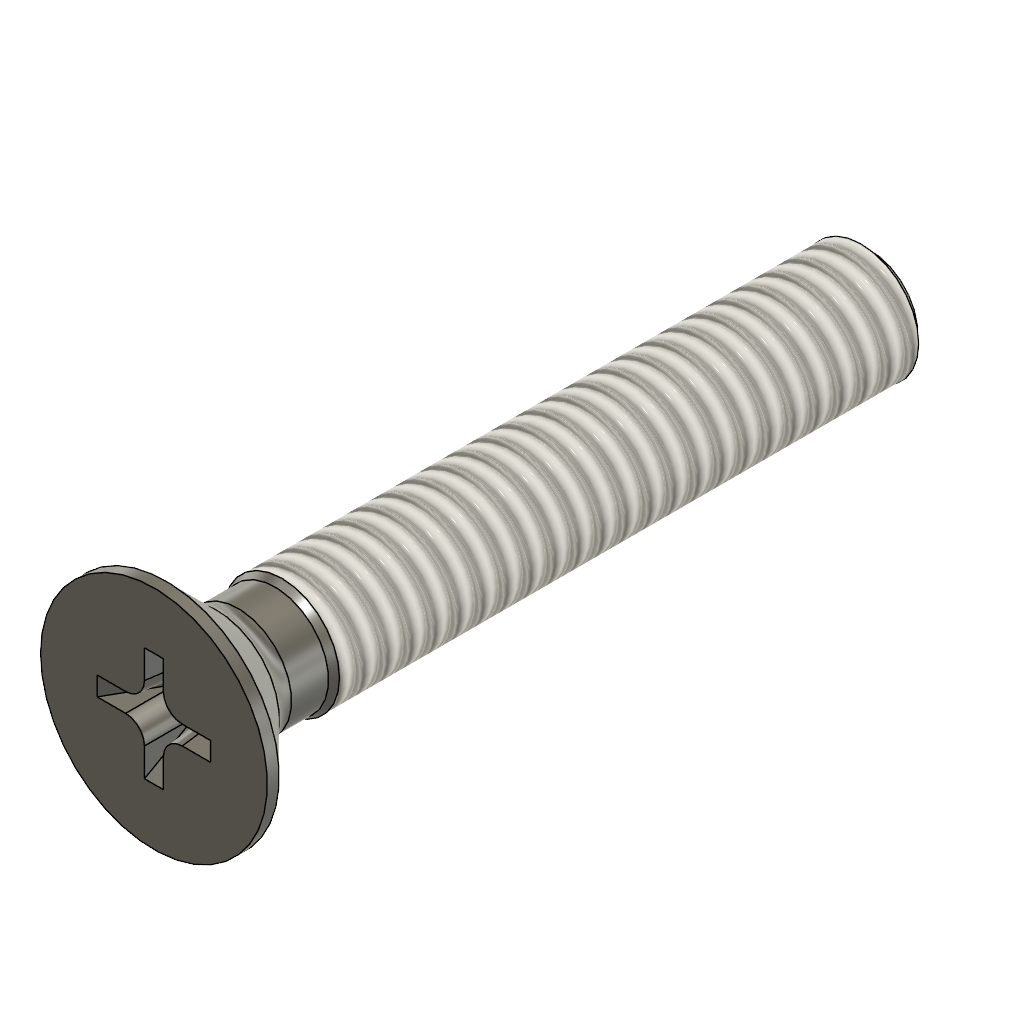
Main-dap (Autodesk Fusion 360 archive; units mm, degrees)
design "Countersunk Head Screw ISO 7046-2 - M2 x 12 - H Steel 4.6 Plain"
description: Countersunk Head Screw ISO 7046-2 - M2 x 12 - H
part number: ISO 7046-2 - M2x12 - H Steel 4.6 Plain
Autodesk Fusion 360 part; units mm, degrees
sketch "Sketch1" plane through (0, 0, 0) normal (0, 1, 0) x (1, 0, 0)
  line L0 (0, -2.1) -> (-1.9, -2.1)
  line L1 (-1.9, -2.1) -> (-1.9, -1.9)
  line L2 (-1.9, -1.9) -> (-0.9, -0.9)
  line L3 (-1, 0.1) -> (-1, 9.9)
  line L4 (-1, 9.9) -> (0, 9.9)
  line L5 (0, 9.9) -> (0, -2.1)
  line L6 (-0.9, -0.0732) -> (-0.9, -0.9)
  line L7 (-1, 0.1) -> (-0.9, -0.0732)
  dimension "d9" = 2
  dimension "d11" = 3.8
  dimension "d71" = 1.2
  dimension "d72" = 1.8
  dimension "d89" = 9.8
  dimension "d101" = 30
  dimension "d115" = 12
  dimension "d121" = 45
  constraint perpendicular L0 L1
  constraint vertical L3
  constraint perpendicular L3 L4
  constraint perpendicular L0 L5
  constraint collinear origin L0.start L4.end
  constraint horizontal L0
  constraint coincident L2.end L6.end
  constraint coincident L6 L7.end
  constraint coincident L6.start L7.end
  constraint coincident origin L2
  measures "d71" distance of L0 L2.end
  measures "d89" distance of L4 L3.start
  measures "d101" angle of L3 L7
  measures "d115" distance of L0.start L4
  measures "d121" angle of L2 L5
revolve "Revolve1" add sketch "Sketch1" angle 360 about axis through (0, 0, -9.9) along (0, 0, 1) makes body 1
sketch "Sketch2" plane through (0, 0, 2.1) normal (0, 0, 1) x (1, 0, 0)
  line L0 (-0.1583, 0.1583) -> (-0.95, 0.1583)
  line L1 (-0.95, 0.1583) -> (-0.95, -0.1583)
  line L2 (-0.95, -0.1583) -> (-0.1583, -0.1583)
  line L3 (0.1583, -0.95) -> (0.1583, -0.1583)
  line L4 (-0.1583, -0.95) -> (0.1583, -0.95)
  line L5 (-0.1583, -0.1583) -> (-0.1583, -0.95)
  line L6 (0.95, 0.1583) -> (0.1583, 0.1583)
  line L7 (0.95, -0.1583) -> (0.95, 0.1583)
  line L8 (0.1583, -0.1583) -> (0.95, -0.1583)
  line L9 (-0.1583, 0.95) -> (-0.1583, 0.1583)
  line L10 (0.1583, 0.95) -> (-0.1583, 0.95)
  line L11 (0.1583, 0.1583) -> (0.1583, 0.95)
  dimension "d111" = 360
  dimension "d117" = 1.9
  dimension "d122" = 0.3167
  constraint horizontal L0
  constraint perpendicular L0 L1
  constraint vertical L0.start L2.end
  constraint coincident L0.start L9.end
  measures "d117" distance of L4.start L10
  measures "d122" distance of L0 L2
extrude "Extrude1" add sketch "Sketch2" against normal blind 1.2 draft -4 separate body makes body 2
draft "Draft1" angle -30 neutral plane through (0, 0, 2.1) pull (0, 0, 1) 4 faces at (0.922, 0.0248, 1.7) (0.0248, 0.922, 1.7) (-0.922, -0.0248, 1.7) (-0.0248, -0.922, 1.7) on bodies 2
fillet "Fillet3" radius 0.3167 4 edges at (0.1164, 0.1164, 1.5) (0.1164, -0.1164, 1.5) (-0.1164, -0.1164, 1.5) (-0.1164, 0.1164, 1.5) on bodies 2
combine "Combine1" operation cut target body 1 tool bodies 2
thread "Thread1" "ISO Metric profile 2.0 M2x0.4 M2x0.4 6g" major diameter 1.9335 minor diameter 1.478 pitch 0.4 angle 60 resizes the face on face at (-0.9988, 0.0498, -3.3667) on bodies 1
fillet "Fillet5" radius 0.5 1 edges at (-0.8391, 0.3255, 0.9) on bodies 1
sketch "Sketch6" plane through (0, 0, 0) normal (0, 1, 0) x (1, 0, 0)
  line L0 (-0.8, 9.9) -> (-1.02, 9.9)
  line L1 (-1.02, 9.9) -> (-1.02, 9.7)
  line L2 (-1.02, 9.7) -> (-0.8, 9.9)
  line L3 (-1, 9.9) -> (0, 9.9)
  line L4 (0, 0) -> (0, 9.9) construction
  dimension "d102" = 1.02
  dimension "d118" = 0.8
  dimension "d119" = 0.2
  constraint horizontal L0
  constraint perpendicular L0 L1
  constraint coincident L0.start L3
  constraint coincident L4.start origin
  constraint coincident L3.end L4.end
  measures "d102" distance of L4.start L1
  measures "d118" distance of L0.start L4
  measures "d119" distance of L0 L1.end
revolve "Revolve3" cut sketch "Sketch6" angle 360 about axis through (0, 0, 1.75) along (0, 0, 1) bodies 1
equation "d9 = adsk_nomdia"
equation "d11 = adsk_headdia"
equation "adsk_nomlen = 12.00 mm"
equation "adsk_headh = 1.20 mm"
equation "adsk_headdia = 3.80 mm"
equation "adsk_nomdia = 2.00 mm"
equation "adsk_headang = 90.00 deg"
equation "adsk_phildia = 1.90 mm"
equation "d31 = -adsk_phildepth"
equation "adsk_philwidth = adsk_phildia / 6"
equation "adsk_phildepth = 1.20 mm"
equation "d71 = adsk_headh"
equation "d72 = adsk_shnkdia"
equation "adsk_shnkdia = adsk_nomdia - 0.5 * adsk_pitch1"
equation "d89 = adsk_thrlen"
equation "adsk_thrlen = 9.80 mm"
equation "adsk_pitch1 = 0.40 mm"
equation "adsk_startlen = adsk_nomdia * 0.1"
equation "adsk_midfillet = 0.50 mm"
equation "d96 = adsk_midfillet"
equation "d99 = ( adsk_shnkdia / 2 ) * tan(90 deg - adsk_headang / 2) + adsk_headh"
equation "d102 = adsk_nomdia * 0.51"
equation "adsk_endpointdia = adsk_nomdia - adsk_startlen * 2"
equation "d114 = adsk_philwidth"
equation "d115 = adsk_nomlen"
equation "d117 = adsk_phildia"
equation "d118 = adsk_endpointdia / 2"
equation "d119 = adsk_startlen"
equation "d121 = adsk_headang * 0.5"
equation "d122 = adsk_philwidth"
